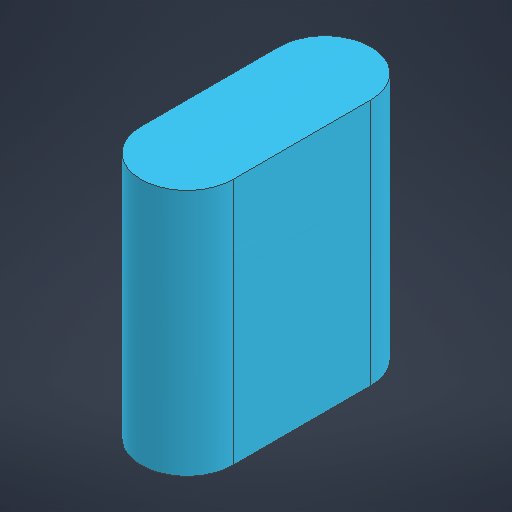
# Autodesk Inventor part: pin sạc 12V 2.6Ah 25A
Saved by Autodesk Inventor 2027 (Build 310192060, 192F)
## iProperties
Created: 2026-07-23
Part Number: pin sạc 12V 2.6Ah 25A
Material: Generic
Document SubType Name: Modeling
Designer: Laptop
Density: 1 g/cm^3
Appearance: Default
Author: Laptop
Autodesk Inventor part; units mm, degrees
ref_plane "YZ Plane" through (0, 0, 0) normal (1, 0, 0) x (0, 1, 0)
ref_plane "XZ Plane" through (0, 0, 0) normal (0, 1, 0) x (-1, 0, 0)
ref_plane "XY Plane" through (0, 0, 0) normal (0, 0, 1) x (1, 0, 0)
sketch "Sketch1" plane through (0, 0, 0) normal (0, 1, 0) x (-1, 0, 0)
  line L0 (26, -13) -> (26, -52)
  line L1 (0, -52) -> (0, -13)
  arc A0 (0, -52) -> (26, -52) centre (13, -52) ccw
  arc A1 (26, -13) -> (0, -13) centre (13, -13) ccw
  point P0 (0, 0)
  constraints: 4 end point, 4 point on circle, 4 tangent, 2 centre point, 1 parallel
extrude "Extrusion1" add sketch "Sketch1" along normal blind 70
body "Solid1"
